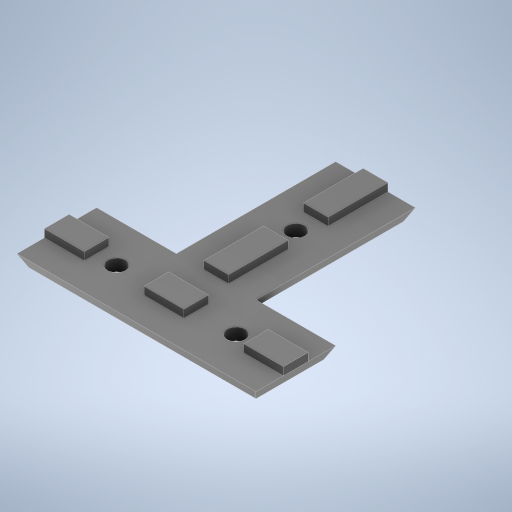
# Autodesk Inventor part: Angular_T
Saved by Autodesk Inventor 2024.3 (Build 283343010, 343A)
## iProperties
Created: 2025-08-07
Part Number: Angular_T
Material: Generic
Document SubType Name: Modeling
Designer: usuario
Density: 1 g/cm^3
Appearance: Smooth - Black
Author: usuario
Autodesk Inventor part; units mm, degrees
ref_plane "YZ Plane" through (0, 0, 0) normal (1, 0, 0) x (0, 1, 0)
ref_plane "XZ Plane" through (0, 0, 0) normal (0, 1, 0) x (-1, 0, 0)
ref_plane "XY Plane" through (0, 0, 0) normal (0, 0, 1) x (1, 0, 0)
sketch "Sketch1" plane through (0, 0, 0) normal (0, 1, 0) x (-1, 0, 0)
  line L0 (30, 0) -> (-30, 0)
  line L1 (-30, 0) -> (-30, -20)
  line L2 (-30, -20) -> (-10, -20)
  line L3 (-10, -20) -> (-10, -60)
  line L4 (-10, -60) -> (10, -60)
  line L5 (10, -60) -> (10, -20)
  line L6 (10, -20) -> (30, -20)
  line L7 (30, -20) -> (30, 0)
  point P0 (0, 0)
  point P1 (0, 0)
  dimension "d0" = 60
  dimension "d1" = 20
  dimension "d2" = 20
  dimension "d3" = 40
  dimension "d4" = 20
  dimension "d5" = 40
  dimension "d6" = 20
  constraints: 16 end point, 3 perpendicular, 2 point on line, 1 coincident, 1 horizontal, 1 horizontal alignment, 1 midpoint, 1 vertical
  measures "d0" distance of L0.start L0.end
  measures "d1" distance of L0.end L1.end
  measures "d2" distance of L1.end L2.end
  measures "d3" distance of L2.end L3.end
  measures "d4" distance of L3.end L4.end
  measures "d5" distance of L4.end L5.end
  measures "d6" distance of L5.end L6.end
extrude "Extrusion1" add sketch "Sketch1" along normal blind 3
sketch "Sketch2" plane through (0, 3, 0) normal (0, 1, 0) x (1, 0, 0)
  line L0 (-3.1, 20) -> (3.1, 20)
  line L1 (3.1, 20) -> (3.1, 60)
  line L2 (3.1, 60) -> (-3.1, 60)
  line L3 (-3.1, 60) -> (-3.1, 20)
  line L4 (10, 60) -> (-10, 60) projected
  line L5 (-30, 6.9) -> (30, 6.9)
  line L6 (30, 6.9) -> (30, 13.1)
  line L7 (30, 13.1) -> (-30, 13.1)
  line L8 (-30, 13.1) -> (-30, 6.9)
  line L9 (30, 0) -> (30, 20) projected
  line L10 (-3.1, 45) -> (3.1, 45)
  line L11 (-3.1, 35) -> (3.1, 35)
  line L12 (-20, 6.9) -> (-20, 13.1)
  line L13 (20, 6.9) -> (20, 13.1)
  line L14 (-5, 6.9) -> (-5, 13.1)
  line L15 (5, 6.9) -> (5, 13.1)
  point P0 (0, 0)
  point P1 (0, 60)
  point P2 (0, 60)
  point P3 (30, 10)
  point P4 (30, 10)
  dimension "d9" = 6.2
  dimension "d10" = 40
  dimension "d11" = 60
  dimension "d12" = 6.2
  dimension "d13" = 15
  dimension "d14" = 15
  dimension "d15" = 10
  dimension "d16" = 10
  dimension "d17" = 15
  dimension "d18" = 15
  constraints: 28 end point, 12 point on line, 8 perpendicular, 4 midpoint, 4 parallel, 2 coincident, 2 horizontal, 1 horizontal alignment, 1 vertical alignment
  measures "d9" distance of L2.end L1.end
  measures "d10" distance of L2.end L0.start
  measures "d11" distance of L7.end L6.end
  measures "d12" distance of L5.end L6.end
  measures "d13" distance between parallel lines of L0 L11
  measures "d14" distance between parallel lines of L2 L10
  measures "d15" distance between parallel lines of L6 L13
  measures "d16" distance between parallel lines of L8 L12
  measures "d17" distance between parallel lines of L13 L15
  measures "d18" distance between parallel lines of L12 L14
extrude "Extrusion2" add sketch "Sketch2" along normal blind 2 contours L3 L11 L1 L0 | L3 L2 L1 L10 | L8 L7 L12 L5 | L14 L7 L15 L5 | L13 L7 L6 L5
sketch "Sketch3" plane through (0, 3, 0) normal (0, 1, 0) x (1, 0, 0)
  line L0 (-30, 0) -> (30, 0) projected
  line L1 (-30, 6.9) -> (-30, 0) projected
  point P0 (0, 0)
  point P1 (-15, 10)
  dimension "d21" = 10
  dimension "d29" = 15
  measures "d21" distance from line of L0 point (-15, 10)
  measures "d29" distance from line of L1 point (-15, 10)
hole "Hole1" at (-15, 3, -10) direction (0, -1, 0) diameter 4.5 end through all
sketch "Sketch4" plane through (0, 3, 0) normal (0, 1, 0) x (1, 0, 0)
  line L0 (30, 0) -> (30, 6.9) projected
  line L1 (-30, 0) -> (30, 0) projected
  point P0 (0, 0)
  point P1 (15, 10)
  dimension "d30" = 15
  dimension "d38" = 10
  measures "d30" distance from line of L0 point (15, 10)
  measures "d38" distance from line of L1 point (15, 10)
hole "Hole2" at (15, 3, -10) direction (0, -1, 0) diameter 4.5 end through all
sketch "Sketch5" plane through (0, 3, 0) normal (0, 1, 0) x (1, 0, 0)
  line L0 (10, 60) -> (3.1, 60) projected
  line L1 (10, 20) -> (10, 60) projected
  point P0 (0, 0)
  point P1 (0, 40)
  dimension "d39" = 20
  dimension "d47" = 10
  measures "d39" distance from line of L0 point (0, 40)
  measures "d47" distance from line of L1 point (0, 40)
hole "Hole3" at (0, 3, -40) direction (0, -1, 0) diameter 4.5 end through all
chamfer "Chamfer1" distance 3 distance2 1.5 1 edges at (0, 0, 0) measured on face at (-10, 1, 0)
chamfer "Chamfer2" distance 3 distance2 1.5 1 edges at (30, 0, -10.7498) measured on face at (30, 1, -9.4665)
chamfer "Chamfer3" distance 3 distance2 1.5 1 edges at (-30, 0, -10.7497) measured on face at (-30, 1, -11.5332)
chamfer "Chamfer4" distance 3 distance2 1.5 1 edges at (-19.25, 0, -20) measured on face at (-22.8333, 2, -20)
chamfer "Chamfer5" distance 3 distance2 1.5 1 edges at (-10, 0, -40) measured on face at (-10, 1.9998, -46.6667)
chamfer "Chamfer6" distance 3 distance2 1.5 1 edges at (0.7498, 0, -60) measured on face at (1.5332, 1, -60)
chamfer "Chamfer7" distance 3 distance2 1.5 1 edges at (10, 0, -39.25) measured on face at (10, 2, -46.1667)
chamfer "Chamfer8" distance 3 distance2 1.5 1 edges at (19.25, 0, -20) measured on face at (22.8333, 2, -20)
equation "\"d14\" = d13"
equation "\"d16\" = d15"
equation "\"d18\" = d17"
body "Solid1"
